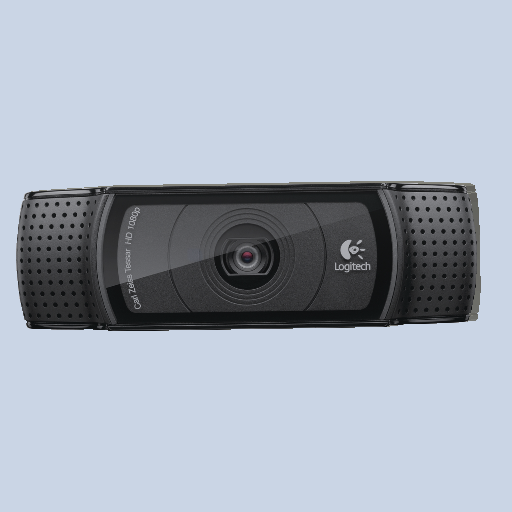
# Autodesk Inventor part: camera c920
Saved by Autodesk Inventor 2025.2 (Build 292293000, 293)
## iProperties
Created: 2014-04-20
Part Number: camera c920
Material: Generic
Document SubType Name: Modeling
Designer: Fahmizal
Density: 1 g/cm^3
Appearance: Silicon Nitride - Polished
Mass: 53.9907 g
Surface Area: 99.7827 cm^2
Volume: 53.9907 cm^3
Author: Fahmizal
Autodesk Inventor part; units mm, degrees
ref_plane "YZ Plane" through (0, 0, 0) normal (1, 0, 0) x (0, 1, 0)
sketch "Sketch1" plane through (0, 0, 0) normal (0, 0, 1) x (1, 0, 0)
  line L0 (0, 0) -> (94, 0)
  line L1 (94, 0) -> (94, 29)
  line L2 (94, 29) -> (0, 29)
  line L3 (0, 29) -> (0, 0)
  dimension "d2" = 29
  dimension "d27" = 94
  constraints: 8 end point, 2 parallel, 1 horizontal, 1 perpendicular
  measures "d2" distance of L0.end L1.end
  measures "d27" distance of L1.end L2.end
extrude "Extrusion4" add sketch "Sketch1" along normal blind 24
ref_plane "Work Plane2" through (0, 0, 34) normal (0, 0, 1) x (1, 0, 0)
sketch "Sketch4" plane through (0, 0, 34) normal (0, 0, 1) x (1, 0, 0)
  line L0 (0, 29.2527) -> (94, 29.2527) construction
  line L1 (94, 29.2527) -> (94, 0) construction
  line L2 (94, 0) -> (0, 0) construction
  line L3 (0, 0) -> (0, 29.2527) construction
  line L4 (0, 0) -> (94, 0) projected
  line L5 (0, 29) -> (0, 0) projected
  dimension "d28" = 24
  dimension "d32" = 94
  dimension "d44" = 0
  dimension "d46" = 0
  constraints: 2 other
  measures "d32" distance of L0.start L0.end
  measures "d44" distance between parallel lines of L4 L2
  measures "d46" distance between parallel lines of L5 L3
decal "Decal2"
sketch "Sketch5" plane through (0, 0, 24) normal (0, 0, 1) x (1, 0, 0)
  line L0 (0, 0) -> (94, 0) projected
  line L1 (94, 0) -> (94, 29) projected
  line L2 (94, 29) -> (0, 29) projected
  line L3 (0, 29) -> (0, 0) projected
  line L4 (1.4426, 26.3708) -> (0, 17.0765)
  line L5 (1.4426, 26.3708) -> (1.8578, 26.754)
  line L6 (1.8578, 26.754) -> (1.8578, 27.9682)
  constraints: 6 end point, 1 parallel, 1 point on line
sketch "Sketch6" plane through (0, 0, 24) normal (0, 0, 1) x (1, 0, 0)
  line L0 (0, 0) -> (94, 0) projected
  line L1 (94, 0) -> (94, 29) projected
  line L2 (94, 29) -> (0, 29) projected
  line L3 (0, 29) -> (0, 0) projected
  line L4 (0, 16.6946) -> (1.0128, 24.7434)
  line L5 (1.0128, 24.7434) -> (1.5352, 26.5505)
  line L6 (1.5352, 26.5505) -> (1.9461, 26.7046)
  line L7 (1.9461, 26.7046) -> (1.9681, 26.8789)
  line L8 (1.9681, 26.8789) -> (1.7407, 27.0275)
  line L9 (1.7407, 27.0275) -> (2.0285, 28.0231)
  line L10 (2.0285, 28.0231) -> (2.774, 28.3605)
  line L11 (2.774, 28.3605) -> (3.7459, 28.4224)
  line L12 (3.7459, 28.4224) -> (5.1088, 28.5091)
  line L13 (5.1088, 28.5091) -> (12.0716, 28.7887)
  line L14 (12.0716, 28.7887) -> (16.8375, 29)
  line L15 (0, 13.3607) -> (0.399, 8.3509)
  line L16 (0.399, 8.3509) -> (0.5637, 6.9114)
  line L17 (0.5637, 6.9114) -> (1.5352, 2.5294)
  line L18 (1.5352, 2.5294) -> (2.0285, 2.3868)
  line L19 (2.0285, 2.3868) -> (1.9167, 2.0002)
  line L20 (1.9167, 2.0002) -> (1.7818, 1.9703)
  line L21 (1.7818, 1.9703) -> (1.9167, 1.2055)
  line L22 (1.9167, 1.2055) -> (2.366, 0.8203)
  line L23 (2.366, 0.8203) -> (4.286, 0.6455)
  line L24 (4.286, 0.6455) -> (11.1575, 0.4753)
  line L25 (11.1575, 0.4753) -> (14.8158, 0.4753)
  line L26 (14.8158, 0.4753) -> (18.1627, 0.3019)
  line L27 (18.1627, 0.3019) -> (18.8679, 0)
  line L28 (47, 23.7227) -> (47, 18.0667) construction
  line L29 (94, 16.6946) -> (92.9872, 24.7434)
  line L30 (92.9872, 24.7434) -> (92.4648, 26.5505)
  line L31 (92.4648, 26.5505) -> (92.0539, 26.7046)
  line L32 (92.0539, 26.7046) -> (92.0319, 26.8789)
  line L33 (92.0319, 26.8789) -> (92.2593, 27.0275)
  line L34 (92.2593, 27.0275) -> (91.9715, 28.0231)
  line L35 (91.9715, 28.0231) -> (91.226, 28.3605)
  line L36 (91.226, 28.3605) -> (90.2541, 28.4224)
  line L37 (90.2541, 28.4224) -> (88.8912, 28.5091)
  line L38 (88.8912, 28.5091) -> (81.9284, 28.7887)
  line L39 (81.9284, 28.7887) -> (77.1625, 29)
  line L40 (94, 13.3607) -> (93.601, 8.3509)
  line L41 (93.601, 8.3509) -> (93.4363, 6.9114)
  line L42 (93.4363, 6.9114) -> (92.4648, 2.5294)
  line L43 (92.4648, 2.5294) -> (91.9715, 2.3868)
  line L44 (91.9715, 2.3868) -> (92.0833, 2.0002)
  line L45 (92.0833, 2.0002) -> (92.2182, 1.9703)
  line L46 (92.2182, 1.9703) -> (92.0833, 1.2055)
  line L47 (92.0833, 1.2055) -> (91.634, 0.8203)
  line L48 (91.634, 0.8203) -> (89.714, 0.6455)
  line L49 (89.714, 0.6455) -> (82.8425, 0.4753)
  line L50 (82.8425, 0.4753) -> (79.1842, 0.4753)
  line L51 (79.1842, 0.4753) -> (75.8373, 0.3019)
  line L52 (75.8373, 0.3019) -> (75.1321, 0)
  line L53 (0, 13.3607) -> (0, 16.6946) construction
  line L54 (0, 16.6946) -> (0, 13.3607) construction
  line L55 (94, 16.6946) -> (94, 29)
  line L56 (94, 29) -> (77.1625, 29)
  line L57 (75.1321, 0) -> (94, 0)
  line L58 (94, 0) -> (94, 13.3607)
  dimension "d48" = 47
  constraints: 110 end point, 26 symmetric about line, 6 collinear, 6 point on line, 4 perpendicular, 3 parallel
  measures "d48" distance between parallel lines of L1 L28
extrude "Extrusion5" cut sketch "Sketch6" against normal blind 24 contours L3 L15 L16 L17 L18 L19 L20 L21 L22 L23 L24 L25 L26 L27 L0 | L52 L51 L50 L49 L48 L47 L46 L45 L44 L43 L42 L41 L40 L1 L0 | L3 L2 L14 L13 L12 L11 L10 L9 L8 L7 L6 L5 L4 | L29 L30 L31 L32 L33 L34 L35 L36 L37 L38 L39 L2 L1
ref_plane "Work Plane3" through (16.8375, 29, 0) normal (0, 1, 0) x (1, 0, 0)
sketch "Sketch8" plane through (16.8375, 29, 0) normal (0, 1, 0) x (1, 0, 0)
  spline S0 degree 2 poles (-16.8375, -23.9597) (-17.1146, -6.7517) (-4.2835, -7.3182) knots 0 0 0 1 1 1
  spline S1 degree 2 poles (-4.2835, -7.3182) (-0.3632, 0.2008) (13.6433, -1.2566) knots 0 0 0 1 1 1
  line L0 (30.1625, -4.2714) -> (30.1625, -21.7894) construction
  spline S2 degree 2 poles (77.1625, -23.9597) (77.4396, -6.7517) (64.6085, -7.3182) knots 0 0 0 1 1 1
  spline S3 degree 2 poles (64.6085, -7.3182) (60.6882, 0.2008) (46.6816, -1.2566) knots 0 0 0 1 1 1
  line L1 (13.6433, -1.2566) -> (46.6816, -1.2566)
  line L2 (-16.8375, -23.9597) -> (-17.3283, -23.9597)
  line L3 (-17.3283, -23.9597) -> (-17.3283, 2.8266)
  line L4 (-17.3283, 2.8266) -> (77.1625, 2.8266)
  line L5 (77.1625, 2.8266) -> (78.7714, 2.8266)
  line L6 (78.7714, 2.8266) -> (78.7714, -23.9597)
  line L7 (78.7714, -23.9597) -> (77.1625, -23.9597)
  point P0 (-16.8375, 0)
  point P1 (-13.1825, -10.4134)
  point P2 (0.8753, -2.5463)
  point P3 (73.5074, -10.4134)
  point P4 (59.4497, -2.5463)
  constraints: 16 end point, 5 symmetric about line, 4 parallel, 1 collinear, 1 perpendicular, 1 vertical, 12 other
extrude "Extrusion6" cut sketch "Sketch8" against normal through all
sketch "Sketch9" plane through (18.8679, 0, 24) normal (0, -1, 0) x (1, 0, 0)
  line L0 (56.2641, -21.9128) -> (56.2641, 0) projected
  line L1 (0, 0) -> (56.2641, 0) projected
  line L2 (0, 0) -> (0, -21.9128) projected
  line L3 (11.6129, -22.7434) -> (44.6512, -22.7434) projected
  line L4 (28.1321, -7.4228) -> (28.1321, -17.1772) construction
  point P0 (-18.8679, -24)
  point P1 (19.6321, -12.3)
  point P2 (36.6321, -12.3)
  dimension "d63" = 56.2641
  dimension "d64" = 8.5
  dimension "d65" = 8.5
  dimension "d66" = 12.3
  constraints: 2 end point, 1 perpendicular
  measures "d63" distance between parallel lines of L0 L2
  measures "d64" distance from line of L4 point (19.632, -12.3)
  measures "d65" distance from line of L4 point (36.632, -12.3)
  measures "d66" distance from line of L1 point (36.632, -12.3)
hole "Hole1" at (38.5, 0, 11.7) at (55.5, 0, 11.7) direction (0, 1, 0) diameter 1.567 depth 7 tip angle 118 thread size "M2x0.4" class "6H" standard "ISO Metric profile"
sketch "Sketch10" plane through (63.5192, 0, 1.2566) normal (0, 0, -1) x (-1, 0, 0)
  line L0 (0, 29) -> (33.0383, 29) projected
  line L1 (0, 29) -> (0, 0) projected
  line L2 (16.5192, 20.1485) -> (16.5192, 6.6294) construction
  point P0 (33.0383, 0)
  point P1 (63.5192, 0)
  point P2 (7.5192, 14.5)
  point P3 (25.5192, 14.5)
  dimension "d28" = 24
  dimension "d74" = 33.0383
  dimension "d75" = 29
  dimension "d76" = 9
  dimension "d77" = 9
  dimension "d78" = 14.5
  constraints: 2 end point, 1 parallel
  measures "d74" distance of L0.start L0.end
  measures "d75" distance of L0.end point (33.038, 0)
  measures "d76" distance from line of L2 point (7.519, 14.5)
  measures "d77" distance from line of L2 point (25.519, 14.5)
  measures "d78" distance from line of point (25.519, 14.5) L0
hole "Hole2" at (56, 14.5, 1.2566) at (38, 14.5, 1.2566) direction (0, 0, 1) diameter 1.567 depth 7 tip angle 118 thread size "M2x0.4" class "6H" standard "ISO Metric profile"
body "Solid2"
